Autodesk Fusion 360 part; units mm, degrees
(part 2 of 3)
sketch "Profile blank sketch" plane through (0, 2, 0) normal (0, 1, 0) x (1, 0, 0) in component "REFERENCE 2020 rail 0 - measured sloped-slot approximation"
  line L0 (0, -19) -> (20, -19)
  line L1 (20, -19) -> (20, -39)
  line L2 (20, -39) -> (0, -39)
  line L3 (0, -39) -> (0, -19)
  dimension "d406" = 19
  dimension "d407" = 20
  dimension "d408" = 39
  constraint vertical origin L0.start
  constraint horizontal L0.start L0.end
  constraint vertical L0.end L1.end
  constraint vertical L0.start L2.end
  constraint horizontal L1.end L2.end
  measures "d406" vertical distance of origin L0.start
  measures "d407" horizontal distance of origin L0.end
  measures "d408" vertical distance of origin L1.end
extrude "Profile blank" add sketch "Profile blank sketch" along normal blind 116 separate body makes body 41 in component "REFERENCE 2020 rail 0 - measured sloped-slot approximation"
ref_plane "WorkPlane2" through (0, 2, 0) normal (0, 1, 0) x (0, 0, 1) in component "REFERENCE 2020 rail 0 - measured sloped-slot approximation"
sketch "Sloped T channel 0 sketch" plane through (0, 2, 0) normal (0, 1, 0) x (1, 0, 0) in component "REFERENCE 2020 rail 0 - measured sloped-slot approximation"
  line L0 (6.86, -19) -> (6.86, -20.5)
  line L1 (6.86, -20.5) -> (4.5, -20.5)
  line L2 (4.5, -20.5) -> (4.5, -22.55)
  line L3 (4.5, -22.55) -> (7.15, -25.2)
  line L4 (7.15, -25.2) -> (12.85, -25.2)
  line L5 (12.85, -25.2) -> (15.5, -22.55)
  line L6 (15.5, -22.55) -> (15.5, -20.5)
  line L7 (15.5, -20.5) -> (13.14, -20.5)
  line L8 (13.14, -20.5) -> (13.14, -19)
  line L9 (13.14, -19) -> (6.86, -19)
  dimension "d413" = 6.86
  dimension "d414" = 19
  dimension "d415" = 20.5
  dimension "d416" = 4.5
  dimension "d417" = 22.55
  dimension "d418" = 7.15
  dimension "d419" = 25.2
  dimension "d420" = 12.85
  dimension "d421" = 15.5
  dimension "d422" = 13.14
  constraint vertical L0.start L0.end
  constraint horizontal L0.end L1.end
  constraint vertical L1.end L2.end
  constraint horizontal L3.end L4.end
  constraint horizontal L2.end L5.end
  constraint vertical L5.end L6.end
  constraint horizontal L1.end L6.end
  constraint horizontal L6.end L7.end
  constraint vertical L7.end L8.end
  constraint horizontal L0.start L8.end
  measures "d413" horizontal distance of origin L0.start
  measures "d414" vertical distance of origin L0.start
  measures "d415" vertical distance of origin L0.end
  measures "d416" horizontal distance of origin L1.end
  measures "d417" vertical distance of origin L2.end
  measures "d418" horizontal distance of origin L3.end
  measures "d419" vertical distance of origin L3.end
  measures "d420" horizontal distance of origin L4.end
  measures "d421" horizontal distance of origin L5.end
  measures "d422" horizontal distance of origin L7.end
extrude "Sloped T channel 0" cut sketch "Sloped T channel 0 sketch" along normal blind 116 bodies 41 in component "REFERENCE 2020 rail 0 - measured sloped-slot approximation"
ref_plane "WorkPlane3" through (0, 2, 0) normal (0, 1, 0) x (0, 0, 1) in component "REFERENCE 2020 rail 0 - measured sloped-slot approximation"
sketch "Sloped T channel 1 sketch" plane through (0, 2, 0) normal (0, 1, 0) x (1, 0, 0) in component "REFERENCE 2020 rail 0 - measured sloped-slot approximation"
  line L0 (20, -25.86) -> (18.5, -25.86)
  line L1 (18.5, -25.86) -> (18.5, -23.5)
  line L2 (18.5, -23.5) -> (16.45, -23.5)
  line L3 (16.45, -23.5) -> (13.8, -26.15)
  line L4 (13.8, -26.15) -> (13.8, -31.85)
  line L5 (13.8, -31.85) -> (16.45, -34.5)
  line L6 (16.45, -34.5) -> (18.5, -34.5)
  line L7 (18.5, -34.5) -> (18.5, -32.14)
  line L8 (18.5, -32.14) -> (20, -32.14)
  line L9 (20, -32.14) -> (20, -25.86)
  dimension "d427" = 20
  dimension "d428" = 25.86
  dimension "d429" = 18.5
  dimension "d430" = 23.5
  dimension "d431" = 16.45
  dimension "d432" = 13.8
  dimension "d433" = 26.15
  dimension "d434" = 31.85
  dimension "d435" = 34.5
  dimension "d436" = 32.14
  constraint horizontal L0.start L0.end
  constraint vertical L0.end L1.end
  constraint horizontal L1.end L2.end
  constraint vertical L3.end L4.end
  constraint vertical L2.end L5.end
  constraint vertical L1.end L6.end
  constraint horizontal L5.end L6.end
  constraint vertical L6.end L7.end
  constraint vertical L0.start L8.end
  constraint horizontal L7.end L8.end
  measures "d427" horizontal distance of origin L0.start
  measures "d428" vertical distance of origin L0.start
  measures "d429" horizontal distance of origin L0.end
  measures "d430" vertical distance of origin L1.end
  measures "d431" horizontal distance of origin L2.end
  measures "d432" horizontal distance of origin L3.end
  measures "d433" vertical distance of origin L3.end
  measures "d434" vertical distance of origin L4.end
  measures "d435" vertical distance of origin L5.end
  measures "d436" vertical distance of origin L7.end
extrude "Sloped T channel 1" cut sketch "Sloped T channel 1 sketch" along normal blind 116 bodies 41 in component "REFERENCE 2020 rail 0 - measured sloped-slot approximation"
ref_plane "WorkPlane4" through (0, 2, 0) normal (0, 1, 0) x (0, 0, 1) in component "REFERENCE 2020 rail 0 - measured sloped-slot approximation"
sketch "Sloped T channel 2 sketch" plane through (0, 2, 0) normal (0, 1, 0) x (1, 0, 0) in component "REFERENCE 2020 rail 0 - measured sloped-slot approximation"
  line L0 (13.14, -39) -> (13.14, -37.5)
  line L1 (13.14, -37.5) -> (15.5, -37.5)
  line L2 (15.5, -37.5) -> (15.5, -35.45)
  line L3 (15.5, -35.45) -> (12.85, -32.8)
  line L4 (12.85, -32.8) -> (7.15, -32.8)
  line L5 (7.15, -32.8) -> (4.5, -35.45)
  line L6 (4.5, -35.45) -> (4.5, -37.5)
  line L7 (4.5, -37.5) -> (6.86, -37.5)
  line L8 (6.86, -37.5) -> (6.86, -39)
  line L9 (6.86, -39) -> (13.14, -39)
  dimension "d441" = 13.14
  dimension "d442" = 39
  dimension "d443" = 37.5
  dimension "d444" = 15.5
  dimension "d445" = 35.45
  dimension "d446" = 12.85
  dimension "d447" = 32.8
  dimension "d448" = 7.15
  dimension "d449" = 4.5
  dimension "d450" = 6.86
  constraint vertical L0.start L0.end
  constraint horizontal L0.end L1.end
  constraint vertical L1.end L2.end
  constraint horizontal L3.end L4.end
  constraint horizontal L2.end L5.end
  constraint vertical L5.end L6.end
  constraint horizontal L1.end L6.end
  constraint horizontal L6.end L7.end
  constraint vertical L7.end L8.end
  constraint horizontal L0.start L8.end
  measures "d441" horizontal distance of origin L0.start
  measures "d442" vertical distance of origin L0.start
  measures "d443" vertical distance of origin L0.end
  measures "d444" horizontal distance of origin L1.end
  measures "d445" vertical distance of origin L2.end
  measures "d446" horizontal distance of origin L3.end
  measures "d447" vertical distance of origin L3.end
  measures "d448" horizontal distance of origin L4.end
  measures "d449" horizontal distance of origin L5.end
  measures "d450" horizontal distance of origin L7.end
extrude "Sloped T channel 2" cut sketch "Sloped T channel 2 sketch" along normal blind 116 bodies 41 in component "REFERENCE 2020 rail 0 - measured sloped-slot approximation"
ref_plane "WorkPlane5" through (0, 2, 0) normal (0, 1, 0) x (0, 0, 1) in component "REFERENCE 2020 rail 0 - measured sloped-slot approximation"
sketch "Sloped T channel 3 sketch" plane through (0, 2, 0) normal (0, 1, 0) x (1, 0, 0) in component "REFERENCE 2020 rail 0 - measured sloped-slot approximation"
  line L0 (0, -32.14) -> (1.5, -32.14)
  line L1 (1.5, -32.14) -> (1.5, -34.5)
  line L2 (1.5, -34.5) -> (3.55, -34.5)
  line L3 (3.55, -34.5) -> (6.2, -31.85)
  line L4 (6.2, -31.85) -> (6.2, -26.15)
  line L5 (6.2, -26.15) -> (3.55, -23.5)
  line L6 (3.55, -23.5) -> (1.5, -23.5)
  line L7 (1.5, -23.5) -> (1.5, -25.86)
  line L8 (1.5, -25.86) -> (0, -25.86)
  line L9 (0, -25.86) -> (0, -32.14)
  dimension "d455" = 32.14
  dimension "d456" = 1.5
  dimension "d457" = 34.5
  dimension "d458" = 3.55
  dimension "d459" = 6.2
  dimension "d460" = 31.85
  dimension "d461" = 26.15
  dimension "d462" = 23.5
  dimension "d463" = 25.86
  constraint vertical origin L0.start
  constraint horizontal L0.start L0.end
  constraint vertical L0.end L1.end
  constraint horizontal L1.end L2.end
  constraint vertical L3.end L4.end
  constraint vertical L2.end L5.end
  constraint vertical L1.end L6.end
  constraint horizontal L5.end L6.end
  constraint vertical L6.end L7.end
  constraint vertical L0.start L8.end
  constraint horizontal L7.end L8.end
  measures "d455" vertical distance of origin L0.start
  measures "d456" horizontal distance of origin L0.end
  measures "d457" vertical distance of origin L1.end
  measures "d458" horizontal distance of origin L2.end
  measures "d459" horizontal distance of origin L3.end
  measures "d460" vertical distance of origin L3.end
  measures "d461" vertical distance of origin L4.end
  measures "d462" vertical distance of origin L5.end
  measures "d463" vertical distance of origin L7.end
extrude "Sloped T channel 3" cut sketch "Sloped T channel 3 sketch" along normal blind 116 bodies 41 in component "REFERENCE 2020 rail 0 - measured sloped-slot approximation"
ref_plane "WorkPlane6" through (0, 2, 0) normal (0, 1, 0) x (0, 0, 1) in component "REFERENCE 2020 rail 0 - measured sloped-slot approximation"
sketch "Reference center bore sketch" plane through (0, 2, 0) normal (0, 1, 0) x (1, 0, 0) in component "REFERENCE 2020 rail 0 - measured sloped-slot approximation"
  circle A0 centre (10, -29) radius 2.5
  dimension "d468" = 10
  dimension "d469" = 29
  dimension "d470" = 5
  measures "d468" horizontal distance of origin A0.centre
  measures "d469" vertical distance of origin A0.centre
  measures "d470" diameter of A0
extrude "Reference center bore" cut sketch "Reference center bore sketch" along normal blind 116 bodies 41 in component "REFERENCE 2020 rail 0 - measured sloped-slot approximation"
ref_plane "WorkPlane1" through (0, 2, 0) normal (0, 1, 0) x (0, 0, 1) in component "REFERENCE 2020 rail 1 - measured sloped-slot approximation"
sketch "Profile blank sketch (2)" plane through (0, 2, 0) normal (0, 1, 0) x (1, 0, 0) in component "REFERENCE 2020 rail 1 - measured sloped-slot approximation"
  line L0 (110, -19) -> (130, -19)
  line L1 (130, -19) -> (130, -39)
  line L2 (130, -39) -> (110, -39)
  line L3 (110, -39) -> (110, -19)
  dimension "d475" = 110
  dimension "d476" = 19
  dimension "d477" = 130
  dimension "d478" = 39
  constraint horizontal L0.start L0.end
  constraint vertical L0.end L1.end
  constraint vertical L0.start L2.end
  constraint horizontal L1.end L2.end
  measures "d475" horizontal distance of origin L0.start
  measures "d476" vertical distance of origin L0.start
  measures "d477" horizontal distance of origin L0.end
  measures "d478" vertical distance of origin L1.end
extrude "Profile blank'" add sketch "Profile blank sketch (2)" along normal blind 116 separate body makes body 42 in component "REFERENCE 2020 rail 1 - measured sloped-slot approximation"
ref_plane "WorkPlane2" through (0, 2, 0) normal (0, 1, 0) x (0, 0, 1) in component "REFERENCE 2020 rail 1 - measured sloped-slot approximation"
sketch "Sloped T channel 0 sketch (2)" plane through (0, 2, 0) normal (0, 1, 0) x (1, 0, 0) in component "REFERENCE 2020 rail 1 - measured sloped-slot approximation"
  line L0 (116.86, -19) -> (116.86, -20.5)
  line L1 (116.86, -20.5) -> (114.5, -20.5)
  line L2 (114.5, -20.5) -> (114.5, -22.55)
  line L3 (114.5, -22.55) -> (117.15, -25.2)
  line L4 (117.15, -25.2) -> (122.85, -25.2)
  line L5 (122.85, -25.2) -> (125.5, -22.55)
  line L6 (125.5, -22.55) -> (125.5, -20.5)
  line L7 (125.5, -20.5) -> (123.14, -20.5)
  line L8 (123.14, -20.5) -> (123.14, -19)
  line L9 (123.14, -19) -> (116.86, -19)
  dimension "d483" = 116.86
  dimension "d484" = 19
  dimension "d485" = 20.5
  dimension "d486" = 114.5
  dimension "d487" = 22.55
  dimension "d488" = 117.15
  dimension "d489" = 25.2
  dimension "d490" = 122.85
  dimension "d491" = 125.5
  dimension "d492" = 123.14
  constraint vertical L0.start L0.end
  constraint horizontal L0.end L1.end
  constraint vertical L1.end L2.end
  constraint horizontal L3.end L4.end
  constraint horizontal L2.end L5.end
  constraint vertical L5.end L6.end
  constraint horizontal L1.end L6.end
  constraint horizontal L6.end L7.end
  constraint vertical L7.end L8.end
  constraint horizontal L0.start L8.end
  measures "d483" horizontal distance of origin L0.start
  measures "d484" vertical distance of origin L0.start
  measures "d485" vertical distance of origin L0.end
  measures "d486" horizontal distance of origin L1.end
  measures "d487" vertical distance of origin L2.end
  measures "d488" horizontal distance of origin L3.end
  measures "d489" vertical distance of origin L3.end
  measures "d490" horizontal distance of origin L4.end
  measures "d491" horizontal distance of origin L5.end
  measures "d492" horizontal distance of origin L7.end
extrude "Sloped T channel 0'" cut sketch "Sloped T channel 0 sketch (2)" along normal blind 116 bodies 42 in component "REFERENCE 2020 rail 1 - measured sloped-slot approximation"
ref_plane "WorkPlane3" through (0, 2, 0) normal (0, 1, 0) x (0, 0, 1) in component "REFERENCE 2020 rail 1 - measured sloped-slot approximation"
sketch "Sloped T channel 1 sketch (2)" plane through (0, 2, 0) normal (0, 1, 0) x (1, 0, 0) in component "REFERENCE 2020 rail 1 - measured sloped-slot approximation"
  line L0 (130, -25.86) -> (128.5, -25.86)
  line L1 (128.5, -25.86) -> (128.5, -23.5)
  line L2 (128.5, -23.5) -> (126.45, -23.5)
  line L3 (126.45, -23.5) -> (123.8, -26.15)
  line L4 (123.8, -26.15) -> (123.8, -31.85)
  line L5 (123.8, -31.85) -> (126.45, -34.5)
  line L6 (126.45, -34.5) -> (128.5, -34.5)
  line L7 (128.5, -34.5) -> (128.5, -32.14)
  line L8 (128.5, -32.14) -> (130, -32.14)
  line L9 (130, -32.14) -> (130, -25.86)
  dimension "d497" = 130
  dimension "d498" = 25.86
  dimension "d499" = 128.5
  dimension "d500" = 23.5
  dimension "d501" = 126.45
  dimension "d502" = 123.8
  dimension "d503" = 26.15
  dimension "d504" = 31.85
  dimension "d505" = 34.5
  dimension "d506" = 32.14
  constraint horizontal L0.start L0.end
  constraint vertical L0.end L1.end
  constraint horizontal L1.end L2.end
  constraint vertical L3.end L4.end
  constraint vertical L2.end L5.end
  constraint vertical L1.end L6.end
  constraint horizontal L5.end L6.end
  constraint vertical L6.end L7.end
  constraint vertical L0.start L8.end
  constraint horizontal L7.end L8.end
  measures "d497" horizontal distance of origin L0.start
  measures "d498" vertical distance of origin L0.start
  measures "d499" horizontal distance of origin L0.end
  measures "d500" vertical distance of origin L1.end
  measures "d501" horizontal distance of origin L2.end
  measures "d502" horizontal distance of origin L3.end
  measures "d503" vertical distance of origin L3.end
  measures "d504" vertical distance of origin L4.end
  measures "d505" vertical distance of origin L5.end
  measures "d506" vertical distance of origin L7.end
extrude "Sloped T channel 1'" cut sketch "Sloped T channel 1 sketch (2)" along normal blind 116 bodies 42 in component "REFERENCE 2020 rail 1 - measured sloped-slot approximation"
ref_plane "WorkPlane4" through (0, 2, 0) normal (0, 1, 0) x (0, 0, 1) in component "REFERENCE 2020 rail 1 - measured sloped-slot approximation"
sketch "Sloped T channel 2 sketch (2)" plane through (0, 2, 0) normal (0, 1, 0) x (1, 0, 0) in component "REFERENCE 2020 rail 1 - measured sloped-slot approximation"
  line L0 (123.14, -39) -> (123.14, -37.5)
  line L1 (123.14, -37.5) -> (125.5, -37.5)
  line L2 (125.5, -37.5) -> (125.5, -35.45)
  line L3 (125.5, -35.45) -> (122.85, -32.8)
  line L4 (122.85, -32.8) -> (117.15, -32.8)
  line L5 (117.15, -32.8) -> (114.5, -35.45)
  line L6 (114.5, -35.45) -> (114.5, -37.5)
  line L7 (114.5, -37.5) -> (116.86, -37.5)
  line L8 (116.86, -37.5) -> (116.86, -39)
  line L9 (116.86, -39) -> (123.14, -39)
  dimension "d511" = 123.14
  dimension "d512" = 39
  dimension "d513" = 37.5
  dimension "d514" = 125.5
  dimension "d515" = 35.45
  dimension "d516" = 122.85
  dimension "d517" = 32.8
  dimension "d518" = 117.15
  dimension "d519" = 114.5
  dimension "d520" = 116.86
  constraint vertical L0.start L0.end
  constraint horizontal L0.end L1.end
  constraint vertical L1.end L2.end
  constraint horizontal L3.end L4.end
  constraint horizontal L2.end L5.end
  constraint vertical L5.end L6.end
  constraint horizontal L1.end L6.end
  constraint horizontal L6.end L7.end
  constraint vertical L7.end L8.end
  constraint horizontal L0.start L8.end
  measures "d511" horizontal distance of origin L0.start
  measures "d512" vertical distance of origin L0.start
  measures "d513" vertical distance of origin L0.end
  measures "d514" horizontal distance of origin L1.end
  measures "d515" vertical distance of origin L2.end
  measures "d516" horizontal distance of origin L3.end
  measures "d517" vertical distance of origin L3.end
  measures "d518" horizontal distance of origin L4.end
  measures "d519" horizontal distance of origin L5.end
  measures "d520" horizontal distance of origin L7.end
extrude "Sloped T channel 2'" cut sketch "Sloped T channel 2 sketch (2)" along normal blind 116 bodies 42 in component "REFERENCE 2020 rail 1 - measured sloped-slot approximation"
ref_plane "WorkPlane5" through (0, 2, 0) normal (0, 1, 0) x (0, 0, 1) in component "REFERENCE 2020 rail 1 - measured sloped-slot approximation"
sketch "Sloped T channel 3 sketch (2)" plane through (0, 2, 0) normal (0, 1, 0) x (1, 0, 0) in component "REFERENCE 2020 rail 1 - measured sloped-slot approximation"
  line L0 (110, -32.14) -> (111.5, -32.14)
  line L1 (111.5, -32.14) -> (111.5, -34.5)
  line L2 (111.5, -34.5) -> (113.55, -34.5)
  line L3 (113.55, -34.5) -> (116.2, -31.85)
  line L4 (116.2, -31.85) -> (116.2, -26.15)
  line L5 (116.2, -26.15) -> (113.55, -23.5)
  line L6 (113.55, -23.5) -> (111.5, -23.5)
  line L7 (111.5, -23.5) -> (111.5, -25.86)
  line L8 (111.5, -25.86) -> (110, -25.86)
  line L9 (110, -25.86) -> (110, -32.14)
  dimension "d525" = 110
  dimension "d526" = 32.14
  dimension "d527" = 111.5
  dimension "d528" = 34.5
  dimension "d529" = 113.55
  dimension "d530" = 116.2
  dimension "d531" = 31.85
  dimension "d532" = 26.15
  dimension "d533" = 23.5
  dimension "d534" = 25.86
  constraint horizontal L0.start L0.end
  constraint vertical L0.end L1.end
  constraint horizontal L1.end L2.end
  constraint vertical L3.end L4.end
  constraint vertical L2.end L5.end
  constraint vertical L1.end L6.end
  constraint horizontal L5.end L6.end
  constraint vertical L6.end L7.end
  constraint vertical L0.start L8.end
  constraint horizontal L7.end L8.end
  measures "d525" horizontal distance of origin L0.start
  measures "d526" vertical distance of origin L0.start
  measures "d527" horizontal distance of origin L0.end
  measures "d528" vertical distance of origin L1.end
  measures "d529" horizontal distance of origin L2.end
  measures "d530" horizontal distance of origin L3.end
  measures "d531" vertical distance of origin L3.end
  measures "d532" vertical distance of origin L4.end
  measures "d533" vertical distance of origin L5.end
  measures "d534" vertical distance of origin L7.end
extrude "Sloped T channel 3'" cut sketch "Sloped T channel 3 sketch (2)" along normal blind 116 bodies 42 in component "REFERENCE 2020 rail 1 - measured sloped-slot approximation"
ref_plane "WorkPlane6" through (0, 2, 0) normal (0, 1, 0) x (0, 0, 1) in component "REFERENCE 2020 rail 1 - measured sloped-slot approximation"
sketch "Reference center bore sketch (2)" plane through (0, 2, 0) normal (0, 1, 0) x (1, 0, 0) in component "REFERENCE 2020 rail 1 - measured sloped-slot approximation"
  circle A0 centre (120, -29) radius 2.5
  dimension "d539" = 120
  dimension "d540" = 29
  dimension "d541" = 5
  measures "d539" horizontal distance of origin A0.centre
  measures "d540" vertical distance of origin A0.centre
  measures "d541" diameter of A0
extrude "Reference center bore'" cut sketch "Reference center bore sketch (2)" along normal blind 116 bodies 42 in component "REFERENCE 2020 rail 1 - measured sloped-slot approximation"
ref_plane "WorkPlane1" through (0, 2, 0) normal (0, 1, 0) x (0, 0, 1) in component "REFERENCE 2020 rail 2 - measured sloped-slot approximation"
sketch "Profile blank sketch (3)" plane through (0, 2, 0) normal (0, 1, 0) x (1, 0, 0) in component "REFERENCE 2020 rail 2 - measured sloped-slot approximation"
  line L0 (220, -19) -> (240, -19)
  line L1 (240, -19) -> (240, -39)
  line L2 (240, -39) -> (220, -39)
  line L3 (220, -39) -> (220, -19)
  dimension "d546" = 220
  dimension "d547" = 19
  dimension "d548" = 240
  dimension "d549" = 39
  constraint horizontal L0.start L0.end
  constraint vertical L0.end L1.end
  constraint vertical L0.start L2.end
  constraint horizontal L1.end L2.end
  measures "d546" horizontal distance of origin L0.start
  measures "d547" vertical distance of origin L0.start
  measures "d548" horizontal distance of origin L0.end
  measures "d549" vertical distance of origin L1.end
extrude "Profile blank''" add sketch "Profile blank sketch (3)" along normal blind 116 separate body makes body 43 in component "REFERENCE 2020 rail 2 - measured sloped-slot approximation"
ref_plane "WorkPlane2" through (0, 2, 0) normal (0, 1, 0) x (0, 0, 1) in component "REFERENCE 2020 rail 2 - measured sloped-slot approximation"
sketch "Sloped T channel 0 sketch (3)" plane through (0, 2, 0) normal (0, 1, 0) x (1, 0, 0) in component "REFERENCE 2020 rail 2 - measured sloped-slot approximation"
  line L0 (226.86, -19) -> (226.86, -20.5)
  line L1 (226.86, -20.5) -> (224.5, -20.5)
  line L2 (224.5, -20.5) -> (224.5, -22.55)
  line L3 (224.5, -22.55) -> (227.15, -25.2)
  line L4 (227.15, -25.2) -> (232.85, -25.2)
  line L5 (232.85, -25.2) -> (235.5, -22.55)
  line L6 (235.5, -22.55) -> (235.5, -20.5)
  line L7 (235.5, -20.5) -> (233.14, -20.5)
  line L8 (233.14, -20.5) -> (233.14, -19)
  line L9 (233.14, -19) -> (226.86, -19)
  dimension "d554" = 226.86
  dimension "d555" = 19
  dimension "d556" = 20.5
  dimension "d557" = 224.5
  dimension "d558" = 22.55
  dimension "d559" = 227.15
  dimension "d560" = 25.2
  dimension "d561" = 232.85
  dimension "d562" = 235.5
  dimension "d563" = 233.14
  constraint vertical L0.start L0.end
  constraint horizontal L0.end L1.end
  constraint vertical L1.end L2.end
  constraint horizontal L3.end L4.end
  constraint horizontal L2.end L5.end
  constraint vertical L5.end L6.end
  constraint horizontal L1.end L6.end
  constraint horizontal L6.end L7.end
  constraint vertical L7.end L8.end
  constraint horizontal L0.start L8.end
  measures "d554" horizontal distance of origin L0.start
  measures "d555" vertical distance of origin L0.start
  measures "d556" vertical distance of origin L0.end
  measures "d557" horizontal distance of origin L1.end
  measures "d558" vertical distance of origin L2.end
  measures "d559" horizontal distance of origin L3.end
  measures "d560" vertical distance of origin L3.end
  measures "d561" horizontal distance of origin L4.end
  measures "d562" horizontal distance of origin L5.end
  measures "d563" horizontal distance of origin L7.end
extrude "Sloped T channel 0''" cut sketch "Sloped T channel 0 sketch (3)" along normal blind 116 bodies 43 in component "REFERENCE 2020 rail 2 - measured sloped-slot approximation"
ref_plane "WorkPlane3" through (0, 2, 0) normal (0, 1, 0) x (0, 0, 1) in component "REFERENCE 2020 rail 2 - measured sloped-slot approximation"
sketch "Sloped T channel 1 sketch (3)" plane through (0, 2, 0) normal (0, 1, 0) x (1, 0, 0) in component "REFERENCE 2020 rail 2 - measured sloped-slot approximation"
  line L0 (240, -25.86) -> (238.5, -25.86)
  line L1 (238.5, -25.86) -> (238.5, -23.5)
  line L2 (238.5, -23.5) -> (236.45, -23.5)
  line L3 (236.45, -23.5) -> (233.8, -26.15)
  line L4 (233.8, -26.15) -> (233.8, -31.85)
  line L5 (233.8, -31.85) -> (236.45, -34.5)
  line L6 (236.45, -34.5) -> (238.5, -34.5)
  line L7 (238.5, -34.5) -> (238.5, -32.14)
  line L8 (238.5, -32.14) -> (240, -32.14)
  line L9 (240, -32.14) -> (240, -25.86)
  dimension "d568" = 240
  dimension "d569" = 25.86
  dimension "d570" = 238.5
  dimension "d571" = 23.5
  dimension "d572" = 236.45
  dimension "d573" = 233.8
  dimension "d574" = 26.15
  dimension "d575" = 31.85
  dimension "d576" = 34.5
  dimension "d577" = 32.14
  constraint horizontal L0.start L0.end
  constraint vertical L0.end L1.end
  constraint horizontal L1.end L2.end
  constraint vertical L3.end L4.end
  constraint vertical L2.end L5.end
  constraint vertical L1.end L6.end
  constraint horizontal L5.end L6.end
  constraint vertical L6.end L7.end
  constraint vertical L0.start L8.end
  constraint horizontal L7.end L8.end
  measures "d568" horizontal distance of origin L0.start
  measures "d569" vertical distance of origin L0.start
  measures "d570" horizontal distance of origin L0.end
  measures "d571" vertical distance of origin L1.end
  measures "d572" horizontal distance of origin L2.end
  measures "d573" horizontal distance of origin L3.end
  measures "d574" vertical distance of origin L3.end
  measures "d575" vertical distance of origin L4.end
  measures "d576" vertical distance of origin L5.end
  measures "d577" vertical distance of origin L7.end
extrude "Sloped T channel 1''" cut sketch "Sloped T channel 1 sketch (3)" along normal blind 116 bodies 43 in component "REFERENCE 2020 rail 2 - measured sloped-slot approximation"
ref_plane "WorkPlane4" through (0, 2, 0) normal (0, 1, 0) x (0, 0, 1) in component "REFERENCE 2020 rail 2 - measured sloped-slot approximation"
sketch "Sloped T channel 2 sketch (3)" plane through (0, 2, 0) normal (0, 1, 0) x (1, 0, 0) in component "REFERENCE 2020 rail 2 - measured sloped-slot approximation"
  line L0 (233.14, -39) -> (233.14, -37.5)
  line L1 (233.14, -37.5) -> (235.5, -37.5)
  line L2 (235.5, -37.5) -> (235.5, -35.45)
  line L3 (235.5, -35.45) -> (232.85, -32.8)
  line L4 (232.85, -32.8) -> (227.15, -32.8)
  line L5 (227.15, -32.8) -> (224.5, -35.45)
  line L6 (224.5, -35.45) -> (224.5, -37.5)
  line L7 (224.5, -37.5) -> (226.86, -37.5)
  line L8 (226.86, -37.5) -> (226.86, -39)
  line L9 (226.86, -39) -> (233.14, -39)
  dimension "d582" = 233.14
  dimension "d583" = 39
  dimension "d584" = 37.5
  dimension "d585" = 235.5
  dimension "d586" = 35.45
  dimension "d587" = 232.85
  dimension "d588" = 32.8
  dimension "d589" = 227.15
  dimension "d590" = 224.5
  dimension "d591" = 226.86
  constraint vertical L0.start L0.end
  constraint horizontal L0.end L1.end
  constraint vertical L1.end L2.end
  constraint horizontal L3.end L4.end
  constraint horizontal L2.end L5.end
  constraint vertical L5.end L6.end
  constraint horizontal L1.end L6.end
  constraint horizontal L6.end L7.end
  constraint vertical L7.end L8.end
  constraint horizontal L0.start L8.end
  measures "d582" horizontal distance of origin L0.start
  measures "d583" vertical distance of origin L0.start
  measures "d584" vertical distance of origin L0.end
  measures "d585" horizontal distance of origin L1.end
  measures "d586" vertical distance of origin L2.end
  measures "d587" horizontal distance of origin L3.end
  measures "d588" vertical distance of origin L3.end
  measures "d589" horizontal distance of origin L4.end
  measures "d590" horizontal distance of origin L5.end
  measures "d591" horizontal distance of origin L7.end
extrude "Sloped T channel 2''" cut sketch "Sloped T channel 2 sketch (3)" along normal blind 116 bodies 43 in component "REFERENCE 2020 rail 2 - measured sloped-slot approximation"
ref_plane "WorkPlane5" through (0, 2, 0) normal (0, 1, 0) x (0, 0, 1) in component "REFERENCE 2020 rail 2 - measured sloped-slot approximation"
sketch "Sloped T channel 3 sketch (3)" plane through (0, 2, 0) normal (0, 1, 0) x (1, 0, 0) in component "REFERENCE 2020 rail 2 - measured sloped-slot approximation"
  line L0 (220, -32.14) -> (221.5, -32.14)
  line L1 (221.5, -32.14) -> (221.5, -34.5)
  line L2 (221.5, -34.5) -> (223.55, -34.5)
  line L3 (223.55, -34.5) -> (226.2, -31.85)
  line L4 (226.2, -31.85) -> (226.2, -26.15)
  line L5 (226.2, -26.15) -> (223.55, -23.5)
  line L6 (223.55, -23.5) -> (221.5, -23.5)
  line L7 (221.5, -23.5) -> (221.5, -25.86)
  line L8 (221.5, -25.86) -> (220, -25.86)
  line L9 (220, -25.86) -> (220, -32.14)
  dimension "d596" = 220
  dimension "d597" = 32.14
  dimension "d598" = 221.5
  dimension "d599" = 34.5
  dimension "d600" = 223.55
  dimension "d601" = 226.2
  dimension "d602" = 31.85
  dimension "d603" = 26.15
  dimension "d604" = 23.5
  dimension "d605" = 25.86
  constraint horizontal L0.start L0.end
  constraint vertical L0.end L1.end
  constraint horizontal L1.end L2.end
  constraint vertical L3.end L4.end
  constraint vertical L2.end L5.end
  constraint vertical L1.end L6.end
  constraint horizontal L5.end L6.end
  constraint vertical L6.end L7.end
  constraint vertical L0.start L8.end
  constraint horizontal L7.end L8.end
  measures "d596" horizontal distance of origin L0.start
  measures "d597" vertical distance of origin L0.start
  measures "d598" horizontal distance of origin L0.end
  measures "d599" vertical distance of origin L1.end
  measures "d600" horizontal distance of origin L2.end
  measures "d601" horizontal distance of origin L3.end
  measures "d602" vertical distance of origin L3.end
  measures "d603" vertical distance of origin L4.end
  measures "d604" vertical distance of origin L5.end
  measures "d605" vertical distance of origin L7.end
extrude "Sloped T channel 3''" cut sketch "Sloped T channel 3 sketch (3)" along normal blind 116 bodies 43 in component "REFERENCE 2020 rail 2 - measured sloped-slot approximation"
ref_plane "WorkPlane6" through (0, 2, 0) normal (0, 1, 0) x (0, 0, 1) in component "REFERENCE 2020 rail 2 - measured sloped-slot approximation"
sketch "Reference center bore sketch (3)" plane through (0, 2, 0) normal (0, 1, 0) x (1, 0, 0) in component "REFERENCE 2020 rail 2 - measured sloped-slot approximation"
  circle A0 centre (230, -29) radius 2.5
  dimension "d610" = 230
  dimension "d611" = 29
  dimension "d612" = 5
  measures "d610" horizontal distance of origin A0.centre
  measures "d611" vertical distance of origin A0.centre
  measures "d612" diameter of A0
extrude "Reference center bore''" cut sketch "Reference center bore sketch (3)" along normal blind 116 bodies 43 in component "REFERENCE 2020 rail 2 - measured sloped-slot approximation"
component "Panel left - restored slot field" placed x (1, 0, 0) y (0, 1, 0) z (0, 0, 1) at (0, 0, 0)
component "Panel right - restored slot field" placed x (1, 0, 0) y (0, 1, 0) z (0, 0, 1) at (0, 0, 0)
component "REFERENCE ONLY - hook insertion corridor 0" placed x (1, 0, 0) y (0, 1, 0) z (0, 0, 1) at (0, 0, 0)
component "REFERENCE ONLY - hook insertion corridor 1" placed x (1, 0, 0) y (0, 1, 0) z (0, 0, 1) at (0, 0, 0)
component "REFERENCE ONLY - hook insertion corridor 2" placed x (1, 0, 0) y (0, 1, 0) z (0, 0, 1) at (0, 0, 0)
component "REFERENCE ONLY - hook insertion corridor 3" placed x (1, 0, 0) y (0, 1, 0) z (0, 0, 1) at (0, 0, 0)
component "REFERENCE ONLY - hook insertion corridor 4" placed x (1, 0, 0) y (0, 1, 0) z (0, 0, 1) at (0, 0, 0)
component "REFERENCE ONLY - hook insertion corridor 5" placed x (1, 0, 0) y (0, 1, 0) z (0, 0, 1) at (0, 0, 0)
component "REFERENCE ONLY - hook insertion corridor 6" placed x (1, 0, 0) y (0, 1, 0) z (0, 0, 1) at (0, 0, 0)
component "REFERENCE ONLY - hook insertion corridor 7" placed x (1, 0, 0) y (0, 1, 0) z (0, 0, 1) at (0, 0, 0)
component "REFERENCE ONLY - hook insertion corridor 8" placed x (1, 0, 0) y (0, 1, 0) z (0, 0, 1) at (0, 0, 0)
component "REFERENCE ONLY - hook insertion corridor 9" placed x (1, 0, 0) y (0, 1, 0) z (0, 0, 1) at (0, 0, 0)
component "REFERENCE ONLY - hook insertion corridor 10" placed x (1, 0, 0) y (0, 1, 0) z (0, 0, 1) at (0, 0, 0)
component "REFERENCE ONLY - hook insertion corridor 11" placed x (1, 0, 0) y (0, 1, 0) z (0, 0, 1) at (0, 0, 0)
component "REFERENCE ONLY - hook insertion corridor 12" placed x (1, 0, 0) y (0, 1, 0) z (0, 0, 1) at (0, 0, 0)
component "REFERENCE ONLY - hook insertion corridor 13" placed x (1, 0, 0) y (0, 1, 0) z (0, 0, 1) at (0, 0, 0)
component "REFERENCE ONLY - hook insertion corridor 14" placed x (1, 0, 0) y (0, 1, 0) z (0, 0, 1) at (0, 0, 0)
component "REFERENCE ONLY - hook insertion corridor 15" placed x (1, 0, 0) y (0, 1, 0) z (0, 0, 1) at (0, 0, 0)
component "REFERENCE ONLY - hook insertion corridor 16" placed x (1, 0, 0) y (0, 1, 0) z (0, 0, 1) at (0, 0, 0)
component "REFERENCE ONLY - hook insertion corridor 17" placed x (1, 0, 0) y (0, 1, 0) z (0, 0, 1) at (0, 0, 0)
component "REFERENCE ONLY - hook insertion corridor 18" placed x (1, 0, 0) y (0, 1, 0) z (0, 0, 1) at (0, 0, 0)
component "REFERENCE ONLY - hook insertion corridor 19" placed x (1, 0, 0) y (0, 1, 0) z (0, 0, 1) at (0, 0, 0)
component "REFERENCE ONLY - hook insertion corridor 20" placed x (1, 0, 0) y (0, 1, 0) z (0, 0, 1) at (0, 0, 0)
component "REFERENCE ONLY - hook insertion corridor 21" placed x (1, 0, 0) y (0, 1, 0) z (0, 0, 1) at (0, 0, 0)
component "REFERENCE ONLY - hook insertion corridor 22" placed x (1, 0, 0) y (0, 1, 0) z (0, 0, 1) at (0, 0, 0)
component "REFERENCE ONLY - hook insertion corridor 23" placed x (1, 0, 0) y (0, 1, 0) z (0, 0, 1) at (0, 0, 0)
component "CONCEPT support blade - retention NOT DESIGNED" placed x (1, 0, 0) y (0, 1, 0) z (0, 0, 1) at (0, 0, 0)
component "CONCEPT support blade - retention NOT DESIGNED (1)" placed x (1, 0, 0) y (0, 1, 0) z (0, 0, 1) at (0, 0, 0)
component "CONCEPT support blade - retention NOT DESIGNED (2)" placed x (1, 0, 0) y (0, 1, 0) z (0, 0, 1) at (0, 0, 0)
component "CONCEPT support blade - retention NOT DESIGNED (3)" placed x (1, 0, 0) y (0, 1, 0) z (0, 0, 1) at (0, 0, 0)
component "CONCEPT support blade - retention NOT DESIGNED (4)" placed x (1, 0, 0) y (0, 1, 0) z (0, 0, 1) at (0, 0, 0)
component "CONCEPT support blade - retention NOT DESIGNED (5)" placed x (1, 0, 0) y (0, 1, 0) z (0, 0, 1) at (0, 0, 0)
component "CONCEPT support blade - retention NOT DESIGNED (6)" placed x (1, 0, 0) y (0, 1, 0) z (0, 0, 1) at (0, 0, 0)
component "CONCEPT support blade - retention NOT DESIGNED (7)" placed x (1, 0, 0) y (0, 1, 0) z (0, 0, 1) at (0, 0, 0)
component "CONCEPT carrier envelope - hardware NOT DESIGNED" placed x (1, 0, 0) y (0, 1, 0) z (0, 0, 1) at (0, 0, 0)
component "CONCEPT carrier envelope - hardware NOT DESIGNED (1)" placed x (1, 0, 0) y (0, 1, 0) z (0, 0, 1) at (0, 0, 0)
component "CONCEPT carrier envelope - hardware NOT DESIGNED (2)" placed x (1, 0, 0) y (0, 1, 0) z (0, 0, 1) at (0, 0, 0)
component "CONCEPT carrier envelope - hardware NOT DESIGNED (3)" placed x (1, 0, 0) y (0, 1, 0) z (0, 0, 1) at (0, 0, 0)
component "CONCEPT carrier envelope - hardware NOT DESIGNED (4)" placed x (1, 0, 0) y (0, 1, 0) z (0, 0, 1) at (0, 0, 0)
component "CONCEPT carrier envelope - hardware NOT DESIGNED (5)" placed x (1, 0, 0) y (0, 1, 0) z (0, 0, 1) at (0, 0, 0)
component "REFERENCE 2020 rail 0 - measured sloped-slot approximation" placed x (1, 0, 0) y (0, 1, 0) z (0, 0, 1) at (0, 0, 0)
component "REFERENCE 2020 rail 1 - measured sloped-slot approximation" placed x (1, 0, 0) y (0, 1, 0) z (0, 0, 1) at (0, 0, 0)
component "REFERENCE 2020 rail 2 - measured sloped-slot approximation" placed x (1, 0, 0) y (0, 1, 0) z (0, 0, 1) at (0, 0, 0)
component "(Unsaved)" placed x (1, 0, 0) y (0, 1, 0) z (0, 0, 1) at (0, 0, 0) in component "REFERENCE ONLY - hook insertion corridor 3"
equation "columns = 6" comment "Even integer 4..14; each cell is 20 mm"
equation "rows = 6" comment "Even integer 4..14"
equation "pitch = 20 mm" comment "Keep for dense SKADIS compatible lattice"
equation "panelWidth = columns * pitch" comment "Nominal module pitch X"
equation "panelHeight = rows * pitch" comment "Nominal module pitch Y"
equation "seamGap = 0.2 mm" comment "Physical envelope shrinks around fixed lattice"
equation "boardThickness = 5 mm" comment "Fit-test with real hooks"
equation "slotWidth = 5 mm" comment "Minimum throat width"
equation "slotHeight = 15 mm" comment "Minimum throat height"
equation "entryRadius = 0.4 mm" comment "Front slot and perimeter edge rounding"
equation "cornerRadius = 6 mm" comment "Plan-view panel corner rounding"
equation "hookClearance = 10 mm" comment "PROVISIONAL: board rear to front of extrusion"
equation "frameZ = boardThickness + hookClearance + carrierThickness" comment "Front extrusion datum"
equation "mountInset = 12 mm" comment "Exterior node inset from outside module edge"
equation "mountBore = 8.4 mm" comment "Clearance around 8 mm metal shoulder"
equation "capDiameter = 18 mm" comment "Visible decorative mounting disk"
equation "capThickness = 5 mm" comment "Metal clamping cap / washer"
equation "seatThickness = 2 mm" comment "Printed rear bearing washer"
equation "screwDiameter = 5 mm" comment "Nominal M5 reference, threads omitted"
equation "screwClearance = 5.5 mm" comment "Cap and spacer bore"
equation "keyWidth = 4 mm" comment "Registration key corridor width"
equation "keyThickness = 2 mm" comment "Rear removable key body"
equation "keyPegDiameter = 3 mm" comment "Rear locating peg"
equation "keySocketDiameter = 3.4 mm" comment "0.2 mm radial starting fit"
equation "keyPegHeight = 0.8 mm" comment "Peg penetration"
equation "keySocketDepth = 1 mm" comment "Blind locating pocket"
equation "profileMouth = 6.28 mm" comment "User measured mouth"
equation "profileCavity = 11 mm" comment "User measured widest cavity"
equation "profileDepth = 6.2 mm" comment "User measured face-to-floor depth"
equation "profileFloor = 5.7 mm" comment "User estimate, lower confidence"
equation "profileLip = 1.5 mm" comment "Unmeasured; tentative comparable catalog value"
equation "profileTaperStart = profileDepth - ( profileCavity - profileFloor ) / 2" comment "Assumed 45-degree inner slopes"
equation "profileBore = 5 mm" comment "Unmeasured central bore, reference only"
equation "nutWidth = 8.8 mm" comment "Provisional low-profile METAL T-nut envelope, not old rectangular carrier"
equation "nutLength = 12 mm" comment "End-loaded anti-rotation metal nut envelope"
equation "nutThickness = 2.7 mm" comment "Thin nut reference; fit/load still unverified"
equation "jointLeg = 18 mm" comment "In-bay angle footprint"
equation "jointThickness = 3 mm" comment "Metal bracket thickness"
equation "jointDepth = 16 mm" comment "Bracket depth within 20 mm rail"
equation "sideScrewLength = 8 mm" comment "M5x8 reference; check against actual bracket and nut"
equation "registerPin = 2 mm" comment "Node-seat locating pins"
equation "registerSocket = 2.4 mm" comment "Starting printed locating clearance"
equation "registerPinHeight = 0.8 mm" comment "Pin into rear socket"
equation "registerSocketDepth = 1 mm" comment "Blind panel socket"
equation "registerOffset = 5 mm" comment "Four pegs at node +/- offset"
equation "wallTabHeight = 24 mm" comment "Tab along extrusion"
equation "wallTabReach = 22 mm" comment "Tab into open bay"
equation "wallAnchorClearance = 6.5 mm" comment "Placeholder wall anchor interface"
equation "wallShim = 0 mm" comment "Only actual leveling shims; no designed rear air gap"
equation "wallDriverDiameter = 12 mm" comment "Clear tool envelope in open bays"
equation "keyDriverDiameter = 5 mm" comment "Short hex-key working-leg envelope"
equation "keyDriverReach = 20 mm" comment "Short hex-key working-leg reach"
equation "supportWidth = 3 mm" comment "Candidate blade width, not a strength-validated part"
equation "supportLength = 12 mm" comment "Candidate blade length along slot column"
equation "hookEnvelopeWidth = 6 mm" comment "Provisional hook sweep width: 5 mm throat plus 0.5 mm each side"
equation "hookLift = 8 mm" comment "Provisional vertical insertion travel"
equation "carrierThickness = 4 mm" comment "Larger hardware stays behind hook clearance datum"
equation "d58 = abs(( 0 mm ) + seamGap / 2)"
equation "d59 = abs(seamGap / 2)"
equation "d60 = panelWidth - seamGap"
equation "d61 = panelHeight - seamGap"
equation "d62 = boardThickness"
equation "d65 = cornerRadius"
equation "d66 = slotWidth"
equation "d67 = slotHeight - slotWidth"
equation "d69 = pitch / 2"
equation "d70 = abs(( 0 mm ) + pitch / 4)"
equation "d71 = abs(( pitch / 2 ) - ( slotHeight - slotWidth ) / 2)"
equation "d72 = boardThickness"
equation "d74 = columns"
equation "d75 = rows"
equation "d76 = pitch"
equation "d77 = pitch"
equation "d78 = slotWidth"
equation "d79 = slotHeight - slotWidth"
equation "d81 = pitch / 2"
equation "d82 = abs(( 0 mm ) + 3 * pitch / 4)"
equation "d83 = abs(( pitch ) - ( slotHeight - slotWidth ) / 2)"
equation "d84 = boardThickness"
equation "d86 = columns"
equation "d87 = rows - 1"
equation "d88 = pitch"
equation "d89 = pitch"
equation "d91 = entryRadius"
equation "d92 = abs(( panelWidth ) + seamGap / 2)"
equation "d93 = abs(seamGap / 2)"
equation "d94 = panelWidth - seamGap"
equation "d95 = panelHeight - seamGap"
equation "d96 = boardThickness"
equation "d99 = cornerRadius"
equation "d100 = slotWidth"
equation "d101 = slotHeight - slotWidth"
equation "d103 = pitch / 2"
equation "d104 = abs(( panelWidth ) + pitch / 4)"
equation "d105 = abs(( pitch / 2 ) - ( slotHeight - slotWidth ) / 2)"
equation "d106 = boardThickness"
equation "d108 = columns"
equation "d109 = rows"
equation "d110 = pitch"
equation "d111 = pitch"
equation "d112 = slotWidth"
equation "d113 = slotHeight - slotWidth"
equation "d115 = pitch / 2"
equation "d116 = abs(( panelWidth ) + 3 * pitch / 4)"
equation "d117 = abs(( pitch ) - ( slotHeight - slotWidth ) / 2)"
equation "d118 = boardThickness"
equation "d120 = columns"
equation "d121 = rows - 1"
equation "d122 = pitch"
equation "d123 = pitch"
equation "d125 = entryRadius"
equation "d126 = boardThickness"
equation "d128 = abs(pitch / 4 + 0 * pitch / 2 - hookEnvelopeWidth / 2)"
equation "d129 = hookEnvelopeWidth"
equation "d130 = panelHeight"
equation "d131 = hookClearance"
equation "d133 = boardThickness"
equation "d135 = abs(pitch / 4 + 1 * pitch / 2 - hookEnvelopeWidth / 2)"
equation "d136 = hookEnvelopeWidth"
equation "d137 = panelHeight"
equation "d138 = hookClearance"
equation "d140 = boardThickness"
equation "d142 = abs(pitch / 4 + 2 * pitch / 2 - hookEnvelopeWidth / 2)"
equation "d143 = hookEnvelopeWidth"
equation "d144 = panelHeight"
equation "d145 = hookClearance"
equation "d147 = boardThickness"
equation "d149 = abs(pitch / 4 + 3 * pitch / 2 - hookEnvelopeWidth / 2)"
equation "d150 = hookEnvelopeWidth"
equation "d151 = panelHeight"
equation "d152 = hookClearance"
equation "d154 = boardThickness"
equation "d156 = abs(pitch / 4 + 4 * pitch / 2 - hookEnvelopeWidth / 2)"
equation "d157 = hookEnvelopeWidth"
equation "d158 = panelHeight"
equation "d159 = hookClearance"
equation "d161 = boardThickness"
equation "d163 = abs(pitch / 4 + 5 * pitch / 2 - hookEnvelopeWidth / 2)"
equation "d164 = hookEnvelopeWidth"
equation "d165 = panelHeight"
equation "d166 = hookClearance"
equation "d168 = boardThickness"
equation "d170 = abs(pitch / 4 + 6 * pitch / 2 - hookEnvelopeWidth / 2)"
equation "d171 = hookEnvelopeWidth"
equation "d172 = panelHeight"
equation "d173 = hookClearance"
equation "d175 = boardThickness"
equation "d177 = abs(pitch / 4 + 7 * pitch / 2 - hookEnvelopeWidth / 2)"
equation "d178 = hookEnvelopeWidth"
equation "d179 = panelHeight"
equation "d180 = hookClearance"
equation "d182 = boardThickness"
equation "d184 = abs(pitch / 4 + 8 * pitch / 2 - hookEnvelopeWidth / 2)"
equation "d185 = hookEnvelopeWidth"
equation "d186 = panelHeight"
equation "d187 = hookClearance"
equation "d189 = boardThickness"
equation "d191 = abs(pitch / 4 + 9 * pitch / 2 - hookEnvelopeWidth / 2)"
equation "d192 = hookEnvelopeWidth"
equation "d193 = panelHeight"
equation "d194 = hookClearance"
equation "d196 = boardThickness"
equation "d198 = abs(pitch / 4 + 10 * pitch / 2 - hookEnvelopeWidth / 2)"
equation "d199 = hookEnvelopeWidth"
equation "d200 = panelHeight"
equation "d201 = hookClearance"
equation "d203 = boardThickness"
equation "d205 = abs(pitch / 4 + 11 * pitch / 2 - hookEnvelopeWidth / 2)"
equation "d206 = hookEnvelopeWidth"
equation "d207 = panelHeight"
equation "d208 = hookClearance"
equation "d210 = boardThickness"
equation "d212 = abs(pitch / 4 + 12 * pitch / 2 - hookEnvelopeWidth / 2)"
equation "d213 = hookEnvelopeWidth"
equation "d214 = panelHeight"
equation "d215 = hookClearance"
equation "d217 = boardThickness"
equation "d219 = abs(pitch / 4 + 13 * pitch / 2 - hookEnvelopeWidth / 2)"
equation "d220 = hookEnvelopeWidth"
equation "d221 = panelHeight"
equation "d222 = hookClearance"
equation "d224 = boardThickness"
equation "d226 = abs(pitch / 4 + 14 * pitch / 2 - hookEnvelopeWidth / 2)"
equation "d227 = hookEnvelopeWidth"
equation "d228 = panelHeight"
equation "d229 = hookClearance"
equation "d231 = boardThickness"
equation "d233 = abs(pitch / 4 + 15 * pitch / 2 - hookEnvelopeWidth / 2)"
equation "d234 = hookEnvelopeWidth"
equation "d235 = panelHeight"
equation "d236 = hookClearance"
equation "d238 = boardThickness"
equation "d240 = abs(pitch / 4 + 16 * pitch / 2 - hookEnvelopeWidth / 2)"
equation "d241 = hookEnvelopeWidth"
equation "d242 = panelHeight"
equation "d243 = hookClearance"
equation "d245 = boardThickness"
equation "d247 = abs(pitch / 4 + 17 * pitch / 2 - hookEnvelopeWidth / 2)"
equation "d248 = hookEnvelopeWidth"
equation "d249 = panelHeight"
equation "d250 = hookClearance"
equation "d252 = boardThickness"
equation "d254 = abs(pitch / 4 + 18 * pitch / 2 - hookEnvelopeWidth / 2)"
equation "d255 = hookEnvelopeWidth"
equation "d256 = panelHeight"
equation "d257 = hookClearance"
equation "d259 = boardThickness"
equation "d261 = abs(pitch / 4 + 19 * pitch / 2 - hookEnvelopeWidth / 2)"
equation "d262 = hookEnvelopeWidth"
equation "d263 = panelHeight"
equation "d264 = hookClearance"
equation "d266 = boardThickness"
equation "d268 = abs(pitch / 4 + 20 * pitch / 2 - hookEnvelopeWidth / 2)"
equation "d269 = hookEnvelopeWidth"
equation "d270 = panelHeight"
equation "d271 = hookClearance"
equation "d273 = boardThickness"
equation "d275 = abs(pitch / 4 + 21 * pitch / 2 - hookEnvelopeWidth / 2)"
equation "d276 = hookEnvelopeWidth"
equation "d277 = panelHeight"
equation "d278 = hookClearance"
equation "d280 = boardThickness"
equation "d282 = abs(pitch / 4 + 22 * pitch / 2 - hookEnvelopeWidth / 2)"
equation "d283 = hookEnvelopeWidth"
equation "d284 = panelHeight"
equation "d285 = hookClearance"
equation "d287 = boardThickness"
equation "d289 = abs(pitch / 4 + 23 * pitch / 2 - hookEnvelopeWidth / 2)"
equation "d290 = hookEnvelopeWidth"
equation "d291 = panelHeight"
equation "d292 = hookClearance"
equation "d294 = boardThickness"
equation "d296 = abs(( pitch / 2 ) - supportWidth / 2)"
equation "d297 = abs(( pitch ) - supportLength / 2)"
equation "d298 = supportWidth"
equation "d299 = supportLength"
equation "d300 = hookClearance"
equation "d302 = boardThickness"
equation "d304 = abs(( pitch / 2 ) - supportWidth / 2)"
equation "d305 = abs(( panelHeight - pitch ) - supportLength / 2)"
equation "d306 = supportWidth"
equation "d307 = supportLength"
equation "d308 = hookClearance"
equation "d310 = boardThickness"
equation "d312 = abs(( panelWidth - pitch / 2 ) - supportWidth / 2)"
equation "d313 = abs(( pitch ) - supportLength / 2)"
equation "d314 = supportWidth"
equation "d315 = supportLength"
equation "d316 = hookClearance"
equation "d318 = boardThickness"
equation "d320 = abs(( panelWidth - pitch / 2 ) - supportWidth / 2)"
equation "d321 = abs(( panelHeight - pitch ) - supportLength / 2)"
equation "d322 = supportWidth"
equation "d323 = supportLength"
equation "d324 = hookClearance"
equation "d326 = boardThickness"
equation "d328 = abs(( panelWidth + pitch / 2 ) - supportWidth / 2)"
equation "d329 = abs(( pitch ) - supportLength / 2)"
equation "d330 = supportWidth"
equation "d331 = supportLength"
equation "d332 = hookClearance"
equation "d334 = boardThickness"
equation "d336 = abs(( panelWidth + pitch / 2 ) - supportWidth / 2)"
equation "d337 = abs(( panelHeight - pitch ) - supportLength / 2)"
equation "d338 = supportWidth"
equation "d339 = supportLength"
equation "d340 = hookClearance"
equation "d342 = boardThickness"
equation "d344 = abs(( 2 * panelWidth - pitch / 2 ) - supportWidth / 2)"
equation "d345 = abs(( pitch ) - supportLength / 2)"
equation "d346 = supportWidth"
equation "d347 = supportLength"
equation "d348 = hookClearance"
equation "d350 = boardThickness"
equation "d352 = abs(( 2 * panelWidth - pitch / 2 ) - supportWidth / 2)"
equation "d353 = abs(( panelHeight - pitch ) - supportLength / 2)"
equation "d354 = supportWidth"
equation "d355 = supportLength"
equation "d356 = hookClearance"
equation "d358 = boardThickness + hookClearance"
equation "d360 = abs(( pitch ) - 8 mm)"
equation "d363 = carrierThickness"
equation "d365 = boardThickness + hookClearance"
equation "d367 = abs(( panelHeight - pitch ) - 8 mm)"
equation "d370 = carrierThickness"
equation "d372 = boardThickness + hookClearance"
equation "d374 = abs(panelWidth - 15 mm)"
equation "d375 = abs(( pitch ) - 8 mm)"
equation "d378 = carrierThickness"
equation "d380 = boardThickness + hookClearance"
equation "d382 = abs(panelWidth - 15 mm)"
equation "d383 = abs(( panelHeight - pitch ) - 8 mm)"
equation "d386 = carrierThickness"
equation "d388 = boardThickness + hookClearance"
equation "d390 = abs(2 * panelWidth - 20 mm)"
equation "d391 = abs(( pitch ) - 8 mm)"
equation "d394 = carrierThickness"
equation "d396 = boardThickness + hookClearance"
equation "d398 = abs(2 * panelWidth - 20 mm)"
equation "d399 = abs(( panelHeight - pitch ) - 8 mm)"
equation "d402 = carrierThickness"
equation "d404 = ( 2 mm ) * 1.0"
equation "d406 = abs(( frameZ ) * -1)"
equation "d407 = abs(( ( 10 mm ) + 10 mm ) * 1)"